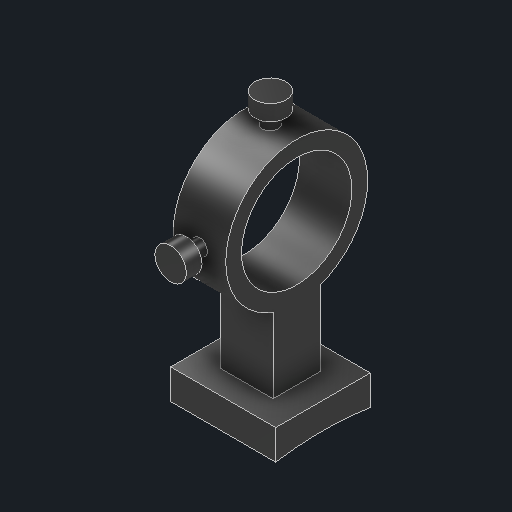
# Autodesk Inventor part: c8n_finder_bracket
Saved by Autodesk Inventor 2027.1 (Build 311270010, 270A)
## iProperties
Created: 2026-11-04
Part Number: c8n_finder_bracket
Material: Generic
Description: Finder bracket (shoe, post, ring with 2 thumbscrews)
Document SubType Name: Modeling
Designer: Claude (from photos)
Density: 1 g/cm^3
Appearance: Glossy - Black
Author: alexg
Autodesk Inventor part; units mm, degrees
ref_plane "Work Plane1" through (0, 104, 0) normal (0, 1, 0) x (-1, 0, 0)
sketch "Shoe sketch" plane through (0, 104, 0) normal (0, 1, 0) x (-1, 0, 0)
  line L0 (-735, -18) -> (-775, -18)
  line L1 (-775, -18) -> (-775, 18)
  line L2 (-775, 18) -> (-735, 18)
  line L3 (-735, 18) -> (-735, -18)
  constraints: 8 end point, 2 parallel, 1 horizontal, 1 perpendicular
extrude "Shoe" add sketch "Shoe sketch" along normal blind 22
ref_plane "Work Plane2" through (700, 0, 0) normal (1, 0, 0) x (0, 1, 0)
sketch "Fit to tube sketch" plane through (700, 0, 0) normal (1, 0, 0) x (0, 1, 0)
  circle A0 centre (0, 0) radius 116
  constraints: 1 centre point
extrude "Fit to tube" cut sketch "Fit to tube sketch" along normal blind 100
ref_plane "Work Plane3" through (0, 126, 0) normal (0, 1, 0) x (-1, 0, 0)
sketch "Post sketch" plane through (0, 126, 0) normal (0, 1, 0) x (-1, 0, 0)
  line L0 (-745, -9) -> (-765, -9)
  line L1 (-765, -9) -> (-765, 9)
  line L2 (-765, 9) -> (-745, 9)
  line L3 (-745, 9) -> (-745, -9)
  constraints: 8 end point, 2 parallel, 1 horizontal, 1 perpendicular
extrude "Post" add sketch "Post sketch" along normal blind 30
ref_plane "Work Plane4" through (745, 0, 0) normal (1, 0, 0) x (0, 1, 0)
sketch "Ring sketch" plane through (745, 0, 0) normal (1, 0, 0) x (0, 1, 0)
  circle A0 centre (180, 0) radius 27
  circle A1 centre (180, 0) radius 21
  constraints: 2 centre point
extrude "Ring" add sketch "Ring sketch" along normal blind 20
ref_plane "Work Plane5" through (0, 206, 0) normal (0, 1, 0) x (-1, 0, 0)
sketch "Top screw sketch" plane through (0, 206, 0) normal (0, 1, 0) x (-1, 0, 0)
  circle A0 centre (-755, 0) radius 3
  constraints: 1 centre point
extrude "Top screw" add sketch "Top screw sketch" along normal blind 8
ref_plane "Work Plane6" through (0, 212, 0) normal (0, 1, 0) x (-1, 0, 0)
sketch "Top thumbscrew sketch" plane through (0, 212, 0) normal (0, 1, 0) x (-1, 0, 0)
  circle A0 centre (-755, 0) radius 6
  constraints: 1 centre point
extrude "Top thumbscrew" add sketch "Top thumbscrew sketch" along normal blind 6
ref_plane "Work Plane7" through (0, 0, 26) normal (0, 0, 1) x (1, 0, 0)
sketch "Side screw sketch" plane through (0, 0, 26) normal (0, 0, 1) x (1, 0, 0)
  circle A0 centre (755, 180) radius 3
  constraints: 1 centre point
extrude "Side screw" add sketch "Side screw sketch" along normal blind 8
ref_plane "Work Plane8" through (0, 0, 32) normal (0, 0, 1) x (1, 0, 0)
sketch "Side thumbscrew sketch" plane through (0, 0, 32) normal (0, 0, 1) x (1, 0, 0)
  circle A0 centre (755, 180) radius 6
  constraints: 1 centre point
extrude "Side thumbscrew" add sketch "Side thumbscrew sketch" along normal blind 6
body "Solid1"
